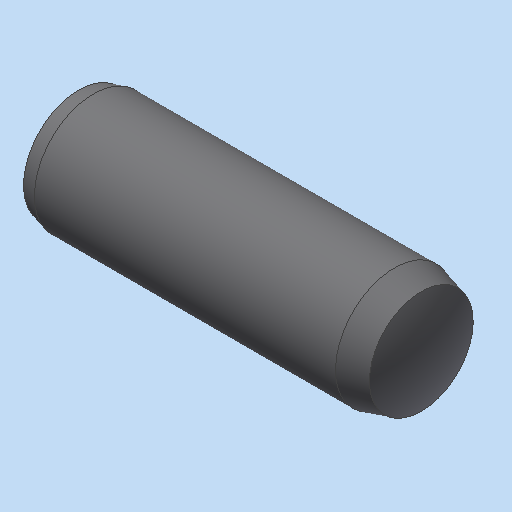
# Autodesk Inventor part: Zylinderstift_DIN_7979D_8_x_24
Saved by Autodesk Inventor 2023.3 (Build 273359000, 359)
## iProperties
Shininess: 64.0
Length Units: 11269
Angle Units: 11279
Time Units: 11290
Mass Units: 11283
Length Display Precision: 3
Angle Display Precision: 2
Compacted: True
Part Number: Zylinderstift_DIN_7979D_8_x_24
Document SubType Name: Modeling
Created: 2004-04-23
Description: =<RBPARTNOTITLE2>
Vendor: NORM8
Designer: C.Fischer
Manufacturer: Standard
Standards Organization: Custom
Density: 7.85 g/cm^3
Material: xStahl_AnP_Dummymaterial
Appearance: Stahl - normal AnP
Mass: 7.74548 g
Surface Area: 8.23973 cm^2
Volume: 0.986686 cm^3
Density: 0.0
Volumn: 0.0
Area: 0.0
PropertySet Name: Model Information
Control State: 0
Master: False
Checked Out: False
CNS_NB: Zylinderstift DIN 7979D 8 x 24
CNS_NN: DIN 7979-D
CNS_NT: Zylinderstift, mit Innengewinde, gehaertet
CNS_NBSYN: Zylinderstift DIN 7979D $NENN.
CNS_LINA: Zylinderstift DIN 7979D 8 x 24
CNS_NENN: 8 x 24
CNS_D: 8.000
CNS_D1: 5.000
CNS_D2: 4.134
CNS_DA: 5.300
CNS_P: 0.800
CNS_L: 24.000
CNS_B: 8.000
CNS_T1: 1.200
CNS_T2: 12.000
CNS_A1: 0.800
CNS_A2: 1.000
CNS_F: 2.620
CNS_KT: X
PSOL_IDENT_0: {C:\partsolutions\data\23d-libs\bosch_bamberg\stifte\scherstifte\din_7979_d.prj},169 {M=Nenngewinde}
PSOL_IDENT_1: ,{VTYP=3D},{NB=Zylinderstift DIN 7979D 8 x 24},{NN=DIN 7979-D},{DATE=26.11.2003},{GEOMDATE=26.11.200
PSOL_IDENT_2: 3},{VERSION=v1},{LINEID=130},{LINESUBID=-1},{WBVAR=}  {NB=Zylinderstift DIN 7979D 8 x 24},{LINA=Zyli
PSOL_IDENT_3: nderstift DIN 7979D 8 x 24},{KT=X},{IDNR=},{NENN=8 x 24},{D=8.000},{D1=5.000},{D2=4.134},{DA=5.300},
PSOL_IDENT_4: {P=0.800},{L=24.000},{B=8.000},{T1=1.200},{T2=12.000},{A1=0.800},{A2=1.000},{F=2.620}
RBDRAWINGMISSINGSPEC: --
RBPARTNOTITLE2: Zylinderstift mit Innengewinde, gehaertet
RBPARTNOTITLE1: Parallel pins with internal thread, hardened
AnP_Kategorie: 4
RBPARTMADEOF: DIN 7979 D - 8 x 24
Title: Zylinderstift DIN 7979D 8 x 24
Author: C.Fischer
Keywords: =<RBPARTMADEOF>
Comments: =<RBSURFACE2>
Revision Number: 01
Autodesk Inventor part; units mm, degrees
sketch "Skizze_4" plane through (0, 0, 0) normal (0, 1, 0) x (-1, 0, 0)
  line L0 (-24, 0) -> (0, 0)
  line L1 (-13.1934, 0) -> (-12, -2.067)
  line L2 (-12, -2.067) -> (-2.2098, -2.067)
  line L3 (-2.2098, -2.067) -> (-1.2, -2.65)
  line L4 (-1.2, -2.65) -> (0, -2.65)
  line L5 (0, -2.65) -> (0, -3.7321)
  line L6 (0, -3.7321) -> (-1, -4)
  line L7 (-1, -4) -> (-21.38, -4)
  line L8 (-21.38, -4) -> (-23.1877, -3.5123)
  arc A0 (-24, 0) -> (-23.1877, -3.5123) centre (-16, 0) ccw
  line L9 (-24, 0) -> (-13.1934, 0)
  constraints: 20 end point, 2 point on circle, 1 centre point
revolve "Revolution1" add sketch "Skizze_4" angle 360 about axis through (24, 0, 0) along (1, 0, 0)
thread "Thread1" size "M5x0.8" class "6H" standard "ANSI Metric M Profile" length 9.7902
ref_plane "IP2_XY" through (0, 0, 0) normal (1, 0, 0) x (0, 0, -1)
ref_plane "IP2_YZ" through (0, 0, 0) normal (0, 0, -1) x (0, 1, 0)
ref_plane "IP1_XY" through (12, 0, 0) normal (1, 0, 0) x (0, 0, -1)
ref_plane "IP1_YZ" through (12, 0, 0) normal (0, 0, -1) x (0, 1, 0)
ref_plane "IP3_XY" through (24, 0, 0) normal (1, 0, 0) x (0, 0, -1)
ref_plane "IP3_YZ" through (24, 0, 0) normal (0, 0, -1) x (0, 1, 0)
